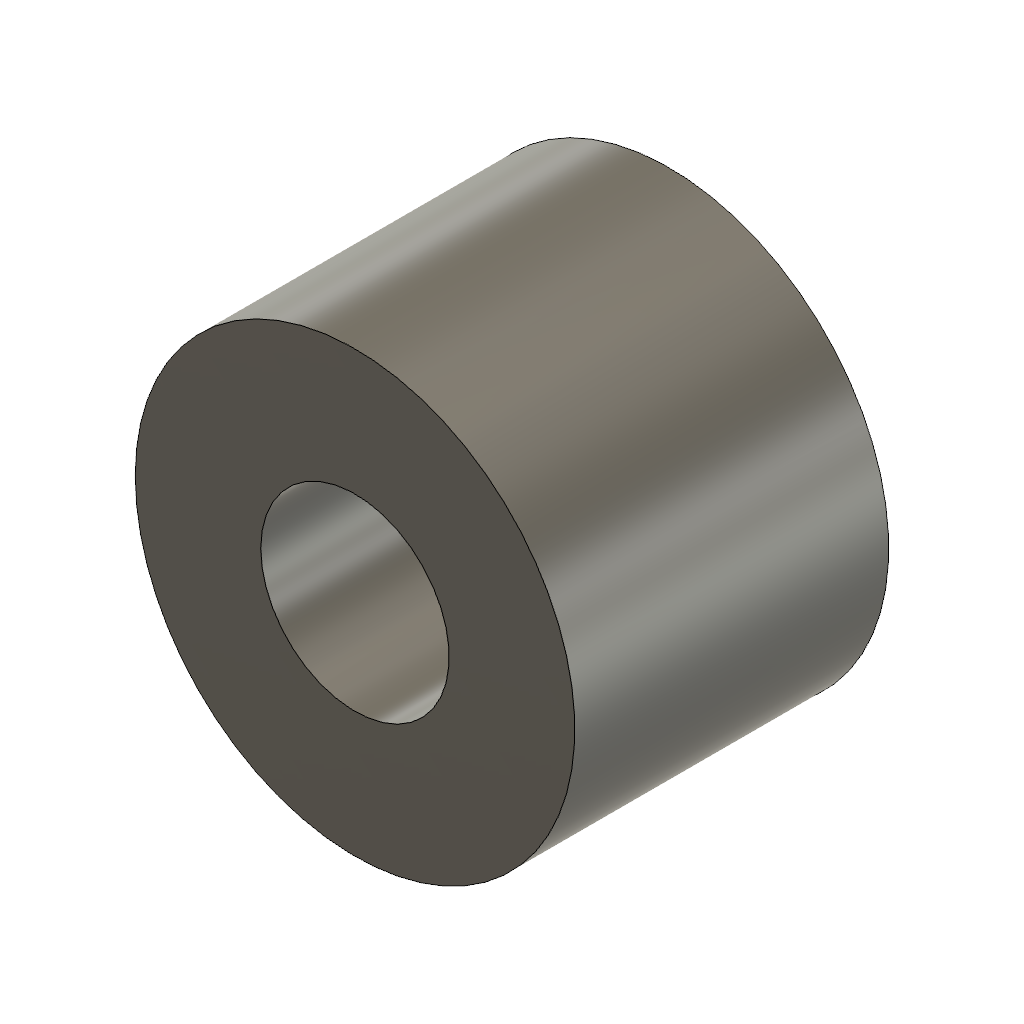
symmetric (Autodesk Fusion 360 design; units mm, degrees)
part number: 2026-10-20-20-56-33-469
Autodesk Fusion 360 part; units mm, degrees
sketch "Sketch1" plane through (0, 0, 0) normal (0, 0, 1) x (1, 0, 0)
  circle A0 centre (0, 0) radius 10
surface "SeedExtrusion" add extruded along (0, 0, 1) between 0 and 20 profiles "Sketch1" section 1 makes body 1
thicken "ProbeThicken" add thickness 4 on both sides 1 faces at (-9.9503, 0.9957, 13.3333) separate body on bodies 1 makes body 2
hidden bodies 1
named bodies: "SeedBody"
